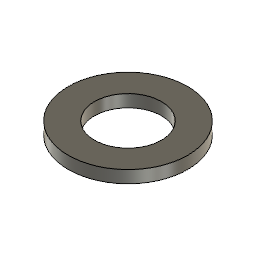
Solenoidklapi kinnitus (Autodesk Fusion 360 archive; units mm, degrees)
design "washer"
Autodesk Fusion 360 part; units mm, degrees
sketch "Sketch1" plane through (0, 0, 0) normal (0, 0, 1) x (1, 0, 0)
  circle A0 centre (0, 0) radius 11.8
  circle A1 centre (0, 0) radius 6.6
  dimension "d1" = 23.6
  dimension "d2" = 13.2
  constraint coincident A0.centre A1.centre
  constraint concentric A0 A1
  measures "d1" diameter of A0
  measures "d2" diameter of A1
extrude "Extrude1" add sketch "Sketch1" along normal blind 2.45

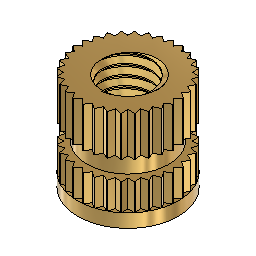
design "_brass+insert+M3.cf30406c-077e-4d83-afc2-e8e3747f2743"
Autodesk Fusion 360 part; units mm, degrees
sketch "Sketch1" plane through (0, 0, 0) normal (1, 0, 0) x (0, 1, 0)
  line L0 (0, 0) -> (-2.625, 0)
  line L1 (-2.625, 0) -> (-2.625, 2.1)
  line L2 (-2.625, 2.1) -> (-2.125, 2.1)
  line L3 (-2.125, 2.1) -> (-2.125, 3.1)
  line L4 (-2.125, 3.1) -> (-2.625, 3.1)
  line L5 (-2.625, 3.1) -> (-2.625, 5.2)
  line L6 (-2.625, 5.2) -> (0, 5.2)
  line L7 (0, 5.2) -> (0, 0)
  dimension "d1" = 5.2
  dimension "d2" = 2.625
  dimension "d3" = 1
  dimension "d4" = 0.5
  measures "d1" distance of L0.start
revolve "Revolve1" add sketch "Sketch1" angle 360 about axis through (0, 0, 5.2) along (0, 0, -1)
hole "Hole1" at (0, 0, 5.2) direction (0, 0, -1) diameter 2.529 depth 2.5 tip angle 118
thread "Thread1" "ISO Metric profile 3.0 M3x0.5 6H" major diameter 3.086 minor diameter 2.529 pitch 0.5 angle 60 modelled right hand crest width 0.0625 on face at (0.063, -1.2629, 4.3667) crest through (1.2645, 0, 5.4812)
sketch "Sketch2" plane through (0, 0, 5.2) normal (0, 0, 1) x (-1, 0, 0)
  circle A0 centre (0, 0) radius 2.625
  line L0 (0.2391, -2.6141) -> (0, -2.375)
  line L1 (0, -2.375) -> (-0.2391, -2.6141)
  line L2 (0, -2.375) -> (0, -2.625) construction
  dimension "d9" = 90
  dimension "d10" = 0.25
  measures "d9" angle of L0 L1
extrude "Extrude1" cut sketch "Sketch2" against normal blind 4.5 contours A0 L0 L1 picked at (0, -2.5409)
pattern_circular "C-Pattern1" count 32 over 360 about axis through (0, 0, 1.75) along (0, 0, 1) of "Extrude1"
equation "d2 = 5.25 mm / 2"

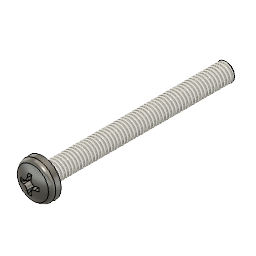
design "Pan Head Screw ISO 7045 - M4 x 40 - H Steel 4.6 Plain"
description: Pan Head Screw ISO 7045 - M4 x 40 - H
part number: ISO 7045 - M4 x 40 - H Steel 4.6 Plain
Autodesk Fusion 360 part; units mm, degrees
sketch "Sketch1" plane through (0, 0, 0) normal (0, 1, 0) x (1, 0, 0)
  line L0 (-2, 1.4) -> (-2, 40)
  line L1 (-2, 40) -> (0, 40)
  line L2 (0, 40) -> (0, -3.1)
  line L3 (-1.8106, 0) -> (-4, 0)
  arc A0 (-3.9381, -1.7712) -> (0, -3.1) centre (0, 3.4) ccw
  line L4 (-2, 1.4) -> (-1.8106, 0.9937)
  line L5 (-1.8106, 0.9937) -> (-1.8106, 0)
  line L6 (-4, 0) -> (-3.9381, -1.7712)
  dimension "d9" = 4
  dimension "d66" = 8
  dimension "d75" = 3.6211
  dimension "d77" = 1.4
  dimension "d78" = 155
  dimension "d103" = 2
  dimension "d111" = 3.1
  dimension "d112" = 40
  constraint perpendicular L0 L1
  constraint collinear origin L2.end L1.end
  constraint perpendicular L0 L3
  constraint coincident origin L3
  constraint vertical L0
  constraint vertical L2
  constraint coincident L2 A0.centre
  constraint perpendicular L3 L5
  constraint coincident L3.start L5.end
  measures "d77" distance of L3 L0.start
  measures "d78" angle of L0 L4
  measures "d103" angle of L2 L6
  measures "d111" distance of L2.end L3
  measures "d112" distance of origin L1
revolve "Revolve1" add sketch "Sketch1" angle 360 about axis through (0, 0, -40) along (0, 0, 1) makes body 1
ref_plane "WorkPlane1" through (0, 0, 3.1) normal (0, 0, 1) x (1, 0, 0)
sketch "Sketch2" plane through (0, 0, 3.1) normal (0, 0, 1) x (1, 0, 0)
  line L0 (-0.415, 0.415) -> (-2.2, 0.415)
  line L1 (-0.415, -0.415) -> (-2.2, -0.415)
  line L2 (-2.2, 0.415) -> (-2.2, -0.415)
  line L3 (-0.415, -0.415) -> (-0.415, -2.2)
  line L4 (-0.415, -2.2) -> (0.415, -2.2)
  line L5 (0.415, -0.415) -> (0.415, -2.2)
  line L6 (0.415, -0.415) -> (2.2, -0.415)
  line L7 (2.2, -0.415) -> (2.2, 0.415)
  line L8 (0.415, 0.415) -> (2.2, 0.415)
  line L9 (0.415, 0.415) -> (0.415, 2.2)
  line L10 (0.415, 2.2) -> (-0.415, 2.2)
  line L11 (-0.415, 0.415) -> (-0.415, 2.2)
  dimension "d105" = 0.83
  dimension "d107" = 360
  dimension "d108" = 4.4
  constraint perpendicular L1 L2
  constraint vertical L0.start L1.start
  constraint horizontal L1
  constraint coincident L8.start L9.start
  measures "d105" distance of L0 L1
  measures "d108" distance of L2 L7
extrude "Extrude1" add sketch "Sketch2" against normal blind 2.4 draft -4 separate body makes body 2
draft "Draft1" angle -30 neutral plane through (0, 0, 3.1) pull (0, 0, 1) 4 faces at (-2.1441, -0.0824, 2.3) (-0.0824, -2.1441, 2.3) (2.1441, 0.0824, 2.3) (-0.0824, 2.1441, 2.3) on bodies 2
fillet "Fillet3" radius 0.83 4 edges at (0.3311, 0.3311, 1.9) (-0.3311, 0.3311, 1.9) (0.3311, -0.3311, 1.9) (-0.3311, -0.3311, 1.9) on bodies 2
combine "Combine1" operation cut target body 1 tool bodies 2
fillet "Fillet4" radius 1.2 1 edges at (-3.6716, 1.4241, 1.7712) on bodies 1
thread "Thread1" "ISO Metric profile 4.0 M4x0.7 M4x0.7 6g" major diameter 3.908 minor diameter 3.111 pitch 0.7 angle 60 resizes the face on face at (-1.9901, 0.1991, -27.1333) on bodies 1
fillet "Fillet5" radius 0.4 1 edges at (-1.688, 0.6547, 0) on bodies 1
sketch "Sketch5" plane through (0, 0, 0) normal (0, 1, 0) x (1, 0, 0)
  line L0 (-2.04, 40) -> (-2.04, 39.5706)
  line L1 (-2.04, 39.5706) -> (-1.5706, 40)
  line L2 (0, 40) -> (0, -3.1)
  line L3 (-2.04, 40) -> (0, 40)
  dimension "d114" = 0.4294
  dimension "d115" = 2.04
  dimension "d116" = 0.4694
  constraint coincident L2.start L3.end
  constraint perpendicular L2 L3
  constraint coincident L1.end L3
  constraint perpendicular L0 L3
  measures "d114" distance of L0.end L3
  measures "d115" distance of L0 L2.start
  measures "d116" distance of L0 L1.end
revolve "Revolve2" cut sketch "Sketch5" angle 360 about axis through (0, 0, -40) along (0, 0, 1) bodies 1
equation "d9 = adsk_nomdia"
equation "adsk_nomlen = 40.00 mm"
equation "adsk_headh = 3.10 mm"
equation "adsk_headdia = 8.00 mm"
equation "adsk_nomdia = 4.00 mm"
equation "adsk_phildia = 4.40 mm"
equation "d31 = -adsk_phildepth"
equation "adsk_philwidth = 0.83 mm"
equation "adsk_phildepth = 2.40 mm"
equation "d66 = adsk_headdia"
equation "d71 = adsk_headh"
equation "adsk_thrlen = 38.60 mm"
equation "d75 = adsk_shnkdia"
equation "adsk_shnkdia = 3.62111 mm"
equation "d77 = adsk_nomlen - adsk_thrlen"
equation "adsk_endpointdia = 3.14117 mm"
equation "adsk_startlen = 0.429415 mm"
equation "adsk_ovalrad = 6.50 mm"
equation "adsk_headtoprad = adsk_nomdia * 0.3"
equation "adsk_midfillet = adsk_nomdia * 0.1"
equation "d98 = adsk_midfillet"
equation "adsk_headang = 2.00 deg"
equation "d102 = adsk_headtoprad"
equation "d103 = adsk_headang"
equation "d105 = adsk_philwidth"
equation "d108 = adsk_phildia"
equation "d110 = adsk_philwidth"
equation "d111 = adsk_headh"
equation "d112 = adsk_nomlen"
equation "d113 = ( adsk_nomlen + adsk_headh ) - ( adsk_ovalrad )"
equation "d114 = adsk_startlen"
equation "d115 = adsk_nomdia * 0.51"
equation "d116 = ( adsk_nomdia * 0.51 ) - ( adsk_endpointdia / 2 )"

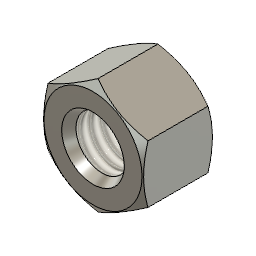
design "Hexagon Regular Nut ISO 4034 - M4 Steel 6 Plain"
description: Hexagon Regular Nut ISO 4034 - M4
part number: ISO 4034 - M4 Steel 6 Plain
Autodesk Fusion 360 part; units mm, degrees
sketch "Sketch1" plane through (0, 0, 0) normal (0, 1, 0) x (1, 0, 0)
  line L0 (0, 0) -> (0, -4.48)
  line L1 (-2, 0) -> (-3.136, 0)
  line L2 (-3.136, 0) -> (-3.696, -0.3233)
  line L3 (-3.696, -0.3233) -> (-3.696, -4.1567)
  line L4 (-3.696, -4.1567) -> (-3.136, -4.48)
  line L5 (-3.136, -4.48) -> (-2, -4.48)
  line L6 (-2, -4.48) -> (-2, 0)
  dimension "d121" = 4
  dimension "d122" = 30
  dimension "d123" = 30
  dimension "d128" = 7.392
  dimension "d172" = 6.272
  dimension "d179" = 4.48
  constraint vertical L0
  constraint coincident L0 L0.end
  constraint coincident origin L0
  constraint horizontal L1
  constraint coincident L0.start L1
  constraint coincident L0.start origin
  constraint coincident L0.end L5
  constraint vertical L1.end L4.end
  measures "d122" angle of L1 L2
  measures "d123" angle of L4 L5
  measures "d179" distance of L1 L5
revolve "Revolve1" add sketch "Sketch1" angle 360 about axis through (0, 0, 0) along (0, 0, 1)
sketch "Sketch8" plane through (0, 0, 4.48) normal (0, 0, 1) x (1, 0, 0)
  line L0 (-3.2, -1.8494) -> (-3.2, 1.8494)
  circle A0 centre (0, 0) radius 2
  circle A1 centre (0, 0) radius 3.696
  dimension "d114" = 3.2
  constraint coincident L0.end A1
  constraint coincident L0.start A1
  constraint vertical L0
  measures "d114" distance of A0.centre L0
extrude "Extrude5" cut sketch "Sketch8" against normal blind 4.48 contours L0 A1 picked at (-3.28, 0.4505)
pattern_circular "C-Pattern2" count 6 over 360 about axis through (0, 0, 1.75) along (0, 0, 1) of "Extrude5"
thread "Thread3" "ISO Metric profile 4.0 M4x0.7 M4x0.7 6H" major diameter 4.1095 minor diameter 3.332 pitch 0.7 angle 60 resizes the face on face at (-1.9975, 0.0997, 2.9867)
sketch "Sketch12" plane through (0, 0, 0) normal (0, 1, 0) x (1, 0, 0)
  line L0 (-2, 0) -> (0, 0)
  line L1 (-0.7067, -2.24) -> (-2, 0)
  line L2 (-2, -4.48) -> (0, -4.48)
  line L3 (-0.7067, -2.24) -> (-2, -4.48)
  line L4 (0, 0) -> (0, -4.48)
  dimension "d169" = 60
  dimension "d177" = 2
  dimension "d178" = 60
  constraint horizontal L0
  constraint coincident L1.start L3.start
  constraint vertical L0.start L2.start
  constraint coincident L2.end L4.end
  constraint coincident L0.end L4.start
  constraint perpendicular L2 L4
  measures "d169" angle of L2 L3
  measures "d177" distance of L0.start L4
  measures "d178" angle of L0 L1
revolve "Revolve3" cut sketch "Sketch12" angle 360 about axis through (0, 0, 1.75) along (0, 0, 1)
equation "adsk_nheig = 4.48 mm"
equation "adsk_maxdia = 7.392 mm"
equation "adsk_nomdia = 4.00 mm"
equation "d89 = -adsk_nheig"
equation "adsk_waflat = 6.40 mm"
equation "d114 = adsk_waflat / 2"
equation "adsk_chamang1 = 30.00 deg"
equation "adsk_chamang2 = 30.00 deg"
equation "d121 = adsk_nomdia"
equation "d122 = adsk_chamang1"
equation "d123 = adsk_chamang2"
equation "d128 = adsk_maxdia"
equation "d163 = adsk_nheig"
equation "adsk_beardia = 6.272 mm"
equation "d172 = adsk_beardia"
equation "d177 = adsk_nomdia * 0.5"
equation "d179 = adsk_nheig"
